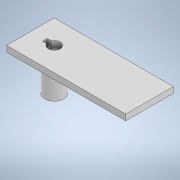
# Autodesk Inventor part: suport_reed_adams
Saved by Autodesk Inventor 2022.6 (Build 266554000, 554)
## iProperties
Created: 2026-03-17
Part Number: suport_reed_adams
Material: Generic
Document SubType Name: Modeling
Designer: Dragos Macovei
Density: 1 g/cm^3
Appearance: Default
Author: Dragos Macovei
Autodesk Inventor part; units mm, degrees
ref_plane "YZ Plane" through (0, 0, 0) normal (1, 0, 0) x (0, 1, 0)
ref_plane "XZ Plane" through (0, 0, 0) normal (0, 1, 0) x (-1, 0, 0)
ref_plane "XY Plane" through (0, 0, 0) normal (0, 0, 1) x (1, 0, 0)
sketch "Sketch1" plane through (0, 0, 0) normal (0, 1, 0) x (-1, 0, 0)
  circle A0 centre (0, 0) radius 2.5
  circle A1 centre (0, 0) radius 4
  dimension "d0" = 5
  dimension "d1" = 8
  constraints: 2 centre point, 2 coincident
  measures "d0" diameter of A0
  measures "d1" diameter of A1
extrude "Extrusion1" add sketch "Sketch1" along normal blind 15
sketch "Sketch2" plane through (0, 15, 0) normal (0, 1, 0) x (1, 0, 0)
  circle A0 centre (0, 0) radius 4 projected
  circle A1 centre (0, 0) radius 2.5 projected
  circle A2 centre (0, 0) radius 4 projected
  line L0 (-4, 0) -> (-4, -1)
  line L1 (-4, -1) -> (-2.0885, -1)
  line L2 (-2.0885, -1) -> (-2.0885, 1)
  line L3 (-2.0885, 1) -> (-4, 1)
  line L4 (-4, 1) -> (-4, 0)
  point P0 (-2.2913, 1)
  point P1 (-3.873, 1)
  point P2 (-3.873, -1)
  point P3 (-2.2913, -1)
  dimension "d4" = 1
  dimension "d5" = 2
  constraints: 10 end point, 4 perpendicular, 2 tangent, 2 vertical, 1 horizontal alignment, 1 point on line, 1 other
  measures "d4" distance of L0.start L0.end
  measures "d5" distance of L1.end L2.end
extrude "Extrusion2" cut sketch "Sketch2" against normal blind 1 contours L3 A1 L1 A0 picked at (-2.9777, -0.2824)
sketch "Sketch4" plane through (0, 15, 0) normal (0, 1, 0) x (1, 0, 0)
  line L0 (-10, 10) -> (40, 10)
  line L1 (40, 10) -> (40, -10)
  line L2 (40, -10) -> (-10, -10)
  line L3 (-10, -10) -> (-10, 10)
  arc A0 (-3.873, -1) -> (-3.873, 1) centre (0, 0) ccw projected
  arc A1 (-3.873, -1) -> (-3.873, 1) centre (0, 0) ccw projected
  arc A2 (-2.2913, -1) -> (-2.2913, 1) centre (0, 0) ccw projected
  line L4 (-2.2913, -1) -> (-3.873, -1) projected
  line L5 (-3.873, 1) -> (-2.2913, 1) projected
  point P0 (40, 0)
  point P1 (-2.9216, -2.7321)
  point P2 (-2.9216, 2.7321)
  dimension "d9" = 10
  dimension "d10" = 10
  dimension "d11" = 10
  dimension "d12" = 40
  constraints: 8 end point, 2 parallel, 1 horizontal, 1 midpoint, 1 perpendicular
  measures "d9" distance from line of L0 point (0, 0)
  measures "d10" distance from line of L2 point (0, 0)
  measures "d11" distance from line of point (0, 0) L3
  measures "d12" distance of point (40, 0) point (0, 0)
extrude "Extrusion3" add sketch "Sketch4" along normal blind 2.5 contours L0 L1 L2 L3 | L4 A2 L5 A0
sketch "Sketch5" plane through (0, 0, 0) normal (0, -1, 0) x (1, 0, 0)
  circle A0 centre (0, 0) radius 4 projected
  circle A1 centre (0, 0) radius 2.5 projected
extrude "Extrusion4" cut sketch "Sketch5" against normal through all contours A1
sketch "Sketch6" plane through (0, 17.5, 0) normal (0, 1, 0) x (1, 0, 0)
  line L0 (-2.2913, -1) -> (-3.873, -1) projected
  arc A0 (-3.873, 1) -> (-3.873, -1) centre (0, 0) ccw projected
  line L1 (-3.873, 1) -> (-2.2913, 1) projected
  circle A1 centre (0, 0) radius 2.5 projected
  point P0 (-2.2913, -2.7321)
extrude "Extrusion5" cut sketch "Sketch6" against normal up to next contours L0 A0 L1 A1
fillet "Fillet2" radius 2 3 edges at (-4, 15, 0) (-3.9681, 14, -0.504) (-3.9681, 14, 0.504)
fillet "Fillet3" radius 2 1 edges at (4, 15, 0)
body "Solid1"
